Autodesk Fusion 360 part; units mm, degrees
(part 2 of 3)
  line L481 (-33.9792, -15.627) -> (-34.3891, -16.0335)
  line L482 (-34.3891, -16.0335) -> (-34.1021, -16.6352)
  line L483 (-34.1021, -16.6352) -> (-33.5283, -16.5724)
  line L484 (-33.5283, -16.5724) -> (-33.2756, -16.7004)
  line L485 (-33.2756, -16.7004) -> (-33.1305, -16.8808)
  line L486 (-33.1305, -16.8808) -> (-33.0698, -17.1043)
  line L487 (-33.0698, -17.1043) -> (-33.1148, -17.3839)
  line L488 (-33.1148, -17.3839) -> (-33.5029, -17.8113)
  line L489 (-33.5029, -17.8113) -> (-33.1848, -18.3972)
  line L490 (-33.1848, -18.3972) -> (-32.615, -18.3045)
  line L491 (-32.615, -18.3045) -> (-32.3559, -18.419)
  line L492 (-32.3559, -18.419) -> (-32.2016, -18.5916)
  line L493 (-32.2016, -18.5916) -> (-32.1293, -18.8116)
  line L494 (-32.1293, -18.8116) -> (-32.1596, -19.0932)
  line L495 (-32.1596, -19.0932) -> (-32.5248, -19.5403)
  line L496 (-32.5248, -19.5403) -> (-32.1765, -20.1087)
  line L497 (-32.1765, -20.1087) -> (-31.6123, -19.9863)
  line L498 (-31.6123, -19.9863) -> (-31.3476, -20.0871)
  line L499 (-31.3476, -20.0871) -> (-31.1844, -20.2514)
  line L500 (-31.1844, -20.2514) -> (-31.1007, -20.4673)
  line L501 (-31.1007, -20.4673) -> (-31.1163, -20.7501)
  line L502 (-31.1163, -20.7501) -> (-31.4576, -21.2157)
  line L503 (-31.4576, -21.2157) -> (-31.08, -21.7651)
  line L504 (-31.08, -21.7651) -> (-30.523, -21.6134)
  line L505 (-30.523, -21.6134) -> (-30.2534, -21.7002)
  line L506 (-30.2534, -21.7002) -> (-30.0818, -21.8557)
  line L507 (-30.0818, -21.8557) -> (-29.9869, -22.067)
  line L508 (-29.9869, -22.067) -> (-29.9877, -22.3502)
  line L509 (-29.9877, -22.3502) -> (-30.3041, -22.833)
  line L510 (-30.3041, -22.833) -> (-29.8983, -23.3619)
  line L511 (-29.8983, -23.3619) -> (-29.35, -23.1812)
  line L512 (-29.35, -23.1812) -> (-29.0762, -23.2538)
  line L513 (-29.0762, -23.2538) -> (-28.8968, -23.4001)
  line L514 (-28.8968, -23.4001) -> (-28.7909, -23.6061)
  line L515 (-28.7909, -23.6061) -> (-28.7769, -23.889)
  line L516 (-28.7769, -23.889) -> (-29.0676, -24.3877)
  line L517 (-29.0676, -24.3877) -> (-28.6346, -24.8947)
  line L518 (-28.6346, -24.8947) -> (-28.0966, -24.6855)
  line L519 (-28.0966, -24.6855) -> (-27.8194, -24.7437)
  line L520 (-27.8194, -24.7437) -> (-27.6325, -24.8804)
  line L521 (-27.6325, -24.8804) -> (-27.516, -25.0806)
  line L522 (-27.516, -25.0806) -> (-27.4872, -25.3623)
  line L523 (-27.4872, -25.3623) -> (-27.7514, -25.8756)
  line L524 (-27.7514, -25.8756) -> (-27.2925, -26.3592)
  line L525 (-27.2925, -26.3592) -> (-26.7661, -26.1221)
  line L526 (-26.7661, -26.1221) -> (-26.4863, -26.1657)
  line L527 (-26.4863, -26.1657) -> (-26.2925, -26.2925)
  line L528 (-26.2925, -26.2925) -> (-26.1657, -26.4863)
  line L529 (-26.1657, -26.4863) -> (-26.1221, -26.7661)
  line L530 (-26.1221, -26.7661) -> (-26.3592, -27.2925)
  line L531 (-26.3592, -27.2925) -> (-25.8756, -27.7514)
  line L532 (-25.8756, -27.7514) -> (-25.3623, -27.4872)
  line L533 (-25.3623, -27.4872) -> (-25.0806, -27.516)
  line L534 (-25.0806, -27.516) -> (-24.8804, -27.6325)
  line L535 (-24.8804, -27.6325) -> (-24.7437, -27.8194)
  line L536 (-24.7437, -27.8194) -> (-24.6855, -28.0966)
  line L537 (-24.6855, -28.0966) -> (-24.8947, -28.6346)
  line L538 (-24.8947, -28.6346) -> (-24.3877, -29.0676)
  line L539 (-24.3877, -29.0676) -> (-23.889, -28.7769)
  line L540 (-23.889, -28.7769) -> (-23.6061, -28.7909)
  line L541 (-23.6061, -28.7909) -> (-23.4001, -28.8968)
  line L542 (-23.4001, -28.8968) -> (-23.2538, -29.0762)
  line L543 (-23.2538, -29.0762) -> (-23.1812, -29.35)
  line L544 (-23.1812, -29.35) -> (-23.3619, -29.8983)
  line L545 (-23.3619, -29.8983) -> (-22.833, -30.3041)
  line L546 (-22.833, -30.3041) -> (-22.3502, -29.9877)
  line L547 (-22.3502, -29.9877) -> (-22.067, -29.9869)
  line L548 (-22.067, -29.9869) -> (-21.8557, -30.0818)
  line L549 (-21.8557, -30.0818) -> (-21.7002, -30.2534)
  line L550 (-21.7002, -30.2534) -> (-21.6134, -30.523)
  line L551 (-21.6134, -30.523) -> (-21.7651, -31.08)
  line L552 (-21.7651, -31.08) -> (-21.2157, -31.4576)
  line L553 (-21.2157, -31.4576) -> (-20.7501, -31.1163)
  line L554 (-20.7501, -31.1163) -> (-20.4673, -31.1007)
  line L555 (-20.4673, -31.1007) -> (-20.2514, -31.1844)
  line L556 (-20.2514, -31.1844) -> (-20.0871, -31.3476)
  line L557 (-20.0871, -31.3476) -> (-19.9863, -31.6123)
  line L558 (-19.9863, -31.6123) -> (-20.1087, -32.1765)
  line L559 (-20.1087, -32.1765) -> (-19.5403, -32.5248)
  line L560 (-19.5403, -32.5248) -> (-19.0932, -32.1596)
  line L561 (-19.0932, -32.1596) -> (-18.8116, -32.1293)
  line L562 (-18.8116, -32.1293) -> (-18.5916, -32.2016)
  line L563 (-18.5916, -32.2016) -> (-18.419, -32.3559)
  line L564 (-18.419, -32.3559) -> (-18.3045, -32.615)
  line L565 (-18.3045, -32.615) -> (-18.3972, -33.1848)
  line L566 (-18.3972, -33.1848) -> (-17.8113, -33.5029)
  line L567 (-17.8113, -33.5029) -> (-17.3839, -33.1148)
  line L568 (-17.3839, -33.1148) -> (-17.1043, -33.0698)
  line L569 (-17.1043, -33.0698) -> (-16.8808, -33.1305)
  line L570 (-16.8808, -33.1305) -> (-16.7004, -33.2756)
  line L571 (-16.7004, -33.2756) -> (-16.5724, -33.5283)
  line L572 (-16.5724, -33.5283) -> (-16.6352, -34.1021)
  line L573 (-16.6352, -34.1021) -> (-16.0335, -34.3891)
  line L574 (-16.0335, -34.3891) -> (-15.627, -33.9792)
  line L575 (-15.627, -33.9792) -> (-15.3501, -33.9196)
  line L576 (-15.3501, -33.9196) -> (-15.1238, -33.9685)
  line L577 (-15.1238, -33.9685) -> (-14.936, -34.104)
  line L578 (-14.936, -34.104) -> (-14.795, -34.3497)
  line L579 (-14.795, -34.3497) -> (-14.8276, -34.926)
  line L580 (-14.8276, -34.926) -> (-14.2117, -35.1811)
  line L581 (-14.2117, -35.1811) -> (-13.8273, -34.7505)
  line L582 (-13.8273, -34.7505) -> (-13.5539, -34.6765)
  line L583 (-13.5539, -34.6765) -> (-13.3253, -34.7135)
  line L584 (-13.3253, -34.7135) -> (-13.1306, -34.839)
  line L585 (-13.1306, -34.839) -> (-12.977, -35.0769)
  line L586 (-12.977, -35.0769) -> (-12.9794, -35.6542)
  line L587 (-12.9794, -35.6542) -> (-12.351, -35.8767)
  line L588 (-12.351, -35.8767) -> (-11.9896, -35.4266)
  line L589 (-11.9896, -35.4266) -> (-11.7204, -35.3383)
  line L590 (-11.7204, -35.3383) -> (-11.4902, -35.3633)
  line L591 (-11.4902, -35.3633) -> (-11.2893, -35.4784)
  line L592 (-11.2893, -35.4784) -> (-11.1234, -35.708)
  line L593 (-11.1234, -35.708) -> (-11.0956, -36.2846)
  line L594 (-11.0956, -36.2846) -> (-10.4564, -36.4739)
  line L595 (-10.4564, -36.4739) -> (-10.1191, -36.0055)
  line L596 (-10.1191, -36.0055) -> (-9.8549, -35.9033)
  line L597 (-9.8549, -35.9033) -> (-9.6237, -35.9162)
  line L598 (-9.6237, -35.9162) -> (-9.417, -36.0206)
  line L599 (-9.417, -36.0206) -> (-9.2394, -36.2412)
  line L600 (-9.2394, -36.2412) -> (-9.1815, -36.8156)
  line L601 (-9.1815, -36.8156) -> (-8.5332, -36.9712)
  line L602 (-8.5332, -36.9712) -> (-8.2208, -36.4858)
  line L603 (-8.2208, -36.4858) -> (-7.9624, -36.3699)
  line L604 (-7.9624, -36.3699) -> (-7.7308, -36.3706)
  line L605 (-7.7308, -36.3706) -> (-7.519, -36.4641)
  line L606 (-7.519, -36.4641) -> (-7.33, -36.6751)
  line L607 (-7.33, -36.6751) -> (-7.2421, -37.2456)
  line L608 (-7.2421, -37.2456) -> (-6.5866, -37.3671)
  line L609 (-6.5866, -37.3671) -> (-6.3001, -36.866)
  line L610 (-6.3001, -36.866) -> (-6.048, -36.7367)
  line L611 (-6.048, -36.7367) -> (-5.8167, -36.7254)
  line L612 (-5.8167, -36.7254) -> (-5.6003, -36.8077)
  line L613 (-5.6003, -36.8077) -> (-5.4005, -37.0085)
  line L614 (-5.4005, -37.0085) -> (-5.2829, -37.5736)
  line L615 (-5.2829, -37.5736) -> (-4.6219, -37.6606)
  line L616 (-4.6219, -37.6606) -> (-4.362, -37.1452)
  line L617 (-4.362, -37.1452) -> (-4.1171, -37.0029)
  line L618 (-4.1171, -37.0029) -> (-3.8867, -36.9795)
  line L619 (-3.8867, -36.9795) -> (-3.6662, -37.0503)
  line L620 (-3.6662, -37.0503) -> (-3.4562, -37.2404)
  line L621 (-3.4562, -37.2404) -> (-3.3092, -37.7986)
  line L622 (-3.3092, -37.7986) -> (-2.6446, -37.8509)
  line L623 (-2.6446, -37.8509) -> (-2.412, -37.3226)
  line L624 (-2.412, -37.3226) -> (-2.1749, -37.1677)
  line L625 (-2.1749, -37.1677) -> (-1.946, -37.1322)
  line L626 (-1.946, -37.1322) -> (-1.7221, -37.1914)
  line L627 (-1.7221, -37.1914) -> (-1.5025, -37.3702)
  line L628 (-1.5025, -37.3702) -> (-1.3264, -37.92)
  line L629 (-1.3264, -37.92) -> (-0.66, -37.9374)
  line L630 (-0.66, -37.9374) -> (-0.4554, -37.3977)
  line L631 (-0.4554, -37.3977) -> (-0.2267, -37.2306)
  line L632 (-0.2267, -37.2306) -> (0, -37.1832)
  line L633 (0, -37.1832) -> (0.2267, -37.2306)
  line L634 (0.2267, -37.2306) -> (0.4554, -37.3977)
  line L635 (0.4554, -37.3977) -> (0.66, -37.9374)
  line L636 (0.66, -37.9374) -> (1.3264, -37.92)
  line L637 (1.3264, -37.92) -> (1.5025, -37.3702)
  line L638 (1.5025, -37.3702) -> (1.7221, -37.1914)
  line L639 (1.7221, -37.1914) -> (1.946, -37.1322)
  line L640 (1.946, -37.1322) -> (2.1749, -37.1677)
  line L641 (2.1749, -37.1677) -> (2.412, -37.3226)
  line L642 (2.412, -37.3226) -> (2.6446, -37.8509)
  line L643 (2.6446, -37.8509) -> (3.3092, -37.7986)
  line L644 (3.3092, -37.7986) -> (3.4562, -37.2404)
  line L645 (3.4562, -37.2404) -> (3.6662, -37.0503)
  line L646 (3.6662, -37.0503) -> (3.8867, -36.9795)
  line L647 (3.8867, -36.9795) -> (4.1171, -37.0029)
  line L648 (4.1171, -37.0029) -> (4.362, -37.1452)
  line L649 (4.362, -37.1452) -> (4.6219, -37.6606)
  line L650 (4.6219, -37.6606) -> (5.2829, -37.5736)
  line L651 (5.2829, -37.5736) -> (5.4005, -37.0085)
  line L652 (5.4005, -37.0085) -> (5.6003, -36.8077)
  line L653 (5.6003, -36.8077) -> (5.8167, -36.7254)
  line L654 (5.8167, -36.7254) -> (6.048, -36.7367)
  line L655 (6.048, -36.7367) -> (6.3001, -36.866)
  line L656 (6.3001, -36.866) -> (6.5866, -37.3671)
  line L657 (6.5866, -37.3671) -> (7.2421, -37.2456)
  line L658 (7.2421, -37.2456) -> (7.33, -36.6751)
  line L659 (7.33, -36.6751) -> (7.519, -36.4641)
  line L660 (7.519, -36.4641) -> (7.7308, -36.3706)
  line L661 (7.7308, -36.3706) -> (7.9624, -36.3699)
  line L662 (7.9624, -36.3699) -> (8.2208, -36.4858)
  line L663 (8.2208, -36.4858) -> (8.5332, -36.9712)
  line L664 (8.5332, -36.9712) -> (9.1815, -36.8156)
  line L665 (9.1815, -36.8156) -> (9.2394, -36.2412)
  line L666 (9.2394, -36.2412) -> (9.417, -36.0206)
  line L667 (9.417, -36.0206) -> (9.6237, -35.9162)
  line L668 (9.6237, -35.9162) -> (9.8549, -35.9033)
  line L669 (9.8549, -35.9033) -> (10.1191, -36.0055)
  line L670 (10.1191, -36.0055) -> (10.4564, -36.4739)
  line L671 (10.4564, -36.4739) -> (11.0956, -36.2846)
  line L672 (11.0956, -36.2846) -> (11.1234, -35.708)
  line L673 (11.1234, -35.708) -> (11.2893, -35.4784)
  line L674 (11.2893, -35.4784) -> (11.4902, -35.3633)
  line L675 (11.4902, -35.3633) -> (11.7204, -35.3383)
  line L676 (11.7204, -35.3383) -> (11.9896, -35.4266)
  line L677 (11.9896, -35.4266) -> (12.351, -35.8767)
  line L678 (12.351, -35.8767) -> (12.9794, -35.6542)
  line L679 (12.9794, -35.6542) -> (12.977, -35.0769)
  line L680 (12.977, -35.0769) -> (13.1306, -34.839)
  line L681 (13.1306, -34.839) -> (13.3253, -34.7135)
  line L682 (13.3253, -34.7135) -> (13.5539, -34.6765)
  line L683 (13.5539, -34.6765) -> (13.8273, -34.7505)
  line L684 (13.8273, -34.7505) -> (14.2117, -35.1811)
  line L685 (14.2117, -35.1811) -> (14.8276, -34.926)
  line L686 (14.8276, -34.926) -> (14.795, -34.3497)
  line L687 (14.795, -34.3497) -> (14.936, -34.104)
  line L688 (14.936, -34.104) -> (15.1238, -33.9685)
  line L689 (15.1238, -33.9685) -> (15.3501, -33.9196)
  line L690 (15.3501, -33.9196) -> (15.627, -33.9792)
  line L691 (15.627, -33.9792) -> (16.0335, -34.3891)
  line L692 (16.0335, -34.3891) -> (16.6352, -34.1021)
  line L693 (16.6352, -34.1021) -> (16.5724, -33.5283)
  line L694 (16.5724, -33.5283) -> (16.7004, -33.2756)
  line L695 (16.7004, -33.2756) -> (16.8808, -33.1305)
  line L696 (16.8808, -33.1305) -> (17.1043, -33.0698)
  line L697 (17.1043, -33.0698) -> (17.3839, -33.1148)
  line L698 (17.3839, -33.1148) -> (17.8113, -33.5029)
  line L699 (17.8113, -33.5029) -> (18.3972, -33.1848)
  line L700 (18.3972, -33.1848) -> (18.3045, -32.615)
  line L701 (18.3045, -32.615) -> (18.419, -32.3559)
  line L702 (18.419, -32.3559) -> (18.5916, -32.2016)
  line L703 (18.5916, -32.2016) -> (18.8116, -32.1293)
  line L704 (18.8116, -32.1293) -> (19.0932, -32.1596)
  line L705 (19.0932, -32.1596) -> (19.5403, -32.5248)
  line L706 (19.5403, -32.5248) -> (20.1087, -32.1765)
  line L707 (20.1087, -32.1765) -> (19.9863, -31.6123)
  line L708 (19.9863, -31.6123) -> (20.0871, -31.3476)
  line L709 (20.0871, -31.3476) -> (20.2514, -31.1844)
  line L710 (20.2514, -31.1844) -> (20.4673, -31.1007)
  line L711 (20.4673, -31.1007) -> (20.7501, -31.1163)
  line L712 (20.7501, -31.1163) -> (21.2157, -31.4576)
  line L713 (21.2157, -31.4576) -> (21.7651, -31.08)
  line L714 (21.7651, -31.08) -> (21.6134, -30.523)
  line L715 (21.6134, -30.523) -> (21.7002, -30.2534)
  line L716 (21.7002, -30.2534) -> (21.8557, -30.0818)
  line L717 (21.8557, -30.0818) -> (22.067, -29.9869)
  line L718 (22.067, -29.9869) -> (22.3502, -29.9877)
  line L719 (22.3502, -29.9877) -> (22.833, -30.3041)
  line L720 (22.833, -30.3041) -> (23.3619, -29.8983)
  line L721 (23.3619, -29.8983) -> (23.1812, -29.35)
  line L722 (23.1812, -29.35) -> (23.2538, -29.0762)
  line L723 (23.2538, -29.0762) -> (23.4001, -28.8968)
  line L724 (23.4001, -28.8968) -> (23.6061, -28.7909)
  line L725 (23.6061, -28.7909) -> (23.889, -28.7769)
  line L726 (23.889, -28.7769) -> (24.3877, -29.0676)
  line L727 (24.3877, -29.0676) -> (24.8947, -28.6346)
  line L728 (24.8947, -28.6346) -> (24.6855, -28.0966)
  line L729 (24.6855, -28.0966) -> (24.7437, -27.8194)
  line L730 (24.7437, -27.8194) -> (24.8804, -27.6325)
  line L731 (24.8804, -27.6325) -> (25.0806, -27.516)
  line L732 (25.0806, -27.516) -> (25.3623, -27.4872)
  line L733 (25.3623, -27.4872) -> (25.8756, -27.7514)
  line L734 (25.8756, -27.7514) -> (26.3592, -27.2925)
  line L735 (26.3592, -27.2925) -> (26.1221, -26.7661)
  line L736 (26.1221, -26.7661) -> (26.1657, -26.4863)
  line L737 (26.1657, -26.4863) -> (26.2925, -26.2925)
  line L738 (26.2925, -26.2925) -> (26.4863, -26.1657)
  line L739 (26.4863, -26.1657) -> (26.7661, -26.1221)
  line L740 (26.7661, -26.1221) -> (27.2925, -26.3592)
  line L741 (27.2925, -26.3592) -> (27.7514, -25.8756)
  line L742 (27.7514, -25.8756) -> (27.4872, -25.3623)
  line L743 (27.4872, -25.3623) -> (27.516, -25.0806)
  line L744 (27.516, -25.0806) -> (27.6325, -24.8804)
  line L745 (27.6325, -24.8804) -> (27.8194, -24.7437)
  line L746 (27.8194, -24.7437) -> (28.0966, -24.6855)
  line L747 (28.0966, -24.6855) -> (28.6346, -24.8947)
  line L748 (28.6346, -24.8947) -> (29.0676, -24.3877)
  line L749 (29.0676, -24.3877) -> (28.7769, -23.889)
  line L750 (28.7769, -23.889) -> (28.7909, -23.6061)
  line L751 (28.7909, -23.6061) -> (28.8968, -23.4001)
  line L752 (28.8968, -23.4001) -> (29.0762, -23.2538)
  line L753 (29.0762, -23.2538) -> (29.35, -23.1812)
  line L754 (29.35, -23.1812) -> (29.8983, -23.3619)
  line L755 (29.8983, -23.3619) -> (30.3041, -22.833)
  line L756 (30.3041, -22.833) -> (29.9877, -22.3502)
  line L757 (29.9877, -22.3502) -> (29.9869, -22.067)
  line L758 (29.9869, -22.067) -> (30.0818, -21.8557)
  line L759 (30.0818, -21.8557) -> (30.2534, -21.7002)
  line L760 (30.2534, -21.7002) -> (30.523, -21.6134)
  line L761 (30.523, -21.6134) -> (31.08, -21.7651)
  line L762 (31.08, -21.7651) -> (31.4576, -21.2157)
  line L763 (31.4576, -21.2157) -> (31.1163, -20.7501)
  line L764 (31.1163, -20.7501) -> (31.1007, -20.4673)
  line L765 (31.1007, -20.4673) -> (31.1844, -20.2514)
  line L766 (31.1844, -20.2514) -> (31.3476, -20.0871)
  line L767 (31.3476, -20.0871) -> (31.6123, -19.9863)
  line L768 (31.6123, -19.9863) -> (32.1765, -20.1087)
  line L769 (32.1765, -20.1087) -> (32.5248, -19.5403)
  line L770 (32.5248, -19.5403) -> (32.1596, -19.0932)
  line L771 (32.1596, -19.0932) -> (32.1293, -18.8116)
  line L772 (32.1293, -18.8116) -> (32.2016, -18.5916)
  line L773 (32.2016, -18.5916) -> (32.3559, -18.419)
  line L774 (32.3559, -18.419) -> (32.615, -18.3045)
  line L775 (32.615, -18.3045) -> (33.1848, -18.3972)
  line L776 (33.1848, -18.3972) -> (33.5029, -17.8113)
  line L777 (33.5029, -17.8113) -> (33.1148, -17.3839)
  line L778 (33.1148, -17.3839) -> (33.0698, -17.1043)
  line L779 (33.0698, -17.1043) -> (33.1305, -16.8808)
  line L780 (33.1305, -16.8808) -> (33.2756, -16.7004)
  line L781 (33.2756, -16.7004) -> (33.5283, -16.5724)
  line L782 (33.5283, -16.5724) -> (34.1021, -16.6352)
  line L783 (34.1021, -16.6352) -> (34.3891, -16.0335)
  line L784 (34.3891, -16.0335) -> (33.9792, -15.627)
  line L785 (33.9792, -15.627) -> (33.9196, -15.3501)
  line L786 (33.9196, -15.3501) -> (33.9685, -15.1238)
  line L787 (33.9685, -15.1238) -> (34.104, -14.936)
  line L788 (34.104, -14.936) -> (34.3497, -14.795)
  line L789 (34.3497, -14.795) -> (34.926, -14.8276)
  line L790 (34.926, -14.8276) -> (35.1811, -14.2117)
  line L791 (35.1811, -14.2117) -> (34.7505, -13.8273)
  line L792 (34.7505, -13.8273) -> (34.6765, -13.5539)
  line L793 (34.6765, -13.5539) -> (34.7135, -13.3253)
  line L794 (34.7135, -13.3253) -> (34.839, -13.1306)
  line L795 (34.839, -13.1306) -> (35.0769, -12.977)
  line L796 (35.0769, -12.977) -> (35.6542, -12.9794)
  line L797 (35.6542, -12.9794) -> (35.8767, -12.351)
  line L798 (35.8767, -12.351) -> (35.4266, -11.9896)
  line L799 (35.4266, -11.9896) -> (35.3383, -11.7204)
  line L800 (35.3383, -11.7204) -> (35.3633, -11.4902)
  line L801 (35.3633, -11.4902) -> (35.4784, -11.2893)
  line L802 (35.4784, -11.2893) -> (35.708, -11.1234)
  line L803 (35.708, -11.1234) -> (36.2846, -11.0956)
  line L804 (36.2846, -11.0956) -> (36.4739, -10.4564)
  line L805 (36.4739, -10.4564) -> (36.0055, -10.1191)
  line L806 (36.0055, -10.1191) -> (35.9033, -9.8549)
  line L807 (35.9033, -9.8549) -> (35.9162, -9.6237)
  line L808 (35.9162, -9.6237) -> (36.0206, -9.417)
  line L809 (36.0206, -9.417) -> (36.2412, -9.2394)
  line L810 (36.2412, -9.2394) -> (36.8156, -9.1815)
  line L811 (36.8156, -9.1815) -> (36.9712, -8.5332)
  line L812 (36.9712, -8.5332) -> (36.4858, -8.2208)
  line L813 (36.4858, -8.2208) -> (36.3699, -7.9624)
  line L814 (36.3699, -7.9624) -> (36.3706, -7.7308)
  line L815 (36.3706, -7.7308) -> (36.4641, -7.519)
  line L816 (36.4641, -7.519) -> (36.6751, -7.33)
  line L817 (36.6751, -7.33) -> (37.2456, -7.2421)
  line L818 (37.2456, -7.2421) -> (37.3671, -6.5866)
  line L819 (37.3671, -6.5866) -> (36.866, -6.3001)
  line L820 (36.866, -6.3001) -> (36.7367, -6.048)
  line L821 (36.7367, -6.048) -> (36.7254, -5.8167)
  line L822 (36.7254, -5.8167) -> (36.8077, -5.6003)
  line L823 (36.8077, -5.6003) -> (37.0085, -5.4005)
  line L824 (37.0085, -5.4005) -> (37.5736, -5.2829)
  line L825 (37.5736, -5.2829) -> (37.6606, -4.6219)
  line L826 (37.6606, -4.6219) -> (37.1452, -4.362)
  line L827 (37.1452, -4.362) -> (37.0029, -4.1171)
  line L828 (37.0029, -4.1171) -> (36.9795, -3.8867)
  line L829 (36.9795, -3.8867) -> (37.0503, -3.6662)
  line L830 (37.0503, -3.6662) -> (37.2404, -3.4562)
  line L831 (37.2404, -3.4562) -> (37.7986, -3.3092)
  line L832 (37.7986, -3.3092) -> (37.8509, -2.6446)
  line L833 (37.8509, -2.6446) -> (37.3226, -2.412)
  line L834 (37.3226, -2.412) -> (37.1677, -2.1749)
  line L835 (37.1677, -2.1749) -> (37.1322, -1.946)
  line L836 (37.1322, -1.946) -> (37.1914, -1.7221)
  line L837 (37.1914, -1.7221) -> (37.3702, -1.5025)
  line L838 (37.3702, -1.5025) -> (37.92, -1.3264)
  line L839 (37.92, -1.3264) -> (37.9374, -0.66)
extrude "Extrude1''''''''''" add sketch "Sketch1 (11)" along normal blind 11 separate body makes body 11 in component "print_pulley_120T"
ref_plane "WorkPlane2" through (0, 0, 7.5) normal (0, 0, 1) x (1, 0, 0) in component "print_pulley_120T"
sketch "Sketch2 (11)" plane through (0, 0, 7.5) normal (0, 0, 1) x (1, 0, 0) in component "print_pulley_120T"
  line L0 (14.607, 0) -> (7.3035, 12.65)
  line L1 (7.3035, 12.65) -> (-7.3035, 12.65)
  line L2 (-7.3035, 12.65) -> (-14.607, 0)
  line L3 (-14.607, 0) -> (-7.3035, -12.65)
  line L4 (-7.3035, -12.65) -> (7.3035, -12.65)
  line L5 (7.3035, -12.65) -> (14.607, 0)
extrude "Extrude2''''''''''" cut sketch "Sketch2 (11)" along normal blind 11 bodies 11 in component "print_pulley_120T"
ref_plane "WorkPlane1" through (0, 0, 7.5) normal (0, 0, 1) x (1, 0, 0) in component "print_pulley_100T"
sketch "Sketch1 (12)" plane through (0, 0, 7.5) normal (0, 0, 1) x (1, 0, 0) in component "print_pulley_100T"
  line L0 (31.5701, -0.66) -> (31.0309, -0.454)
  line L1 (31.0309, -0.454) -> (30.8642, -0.2258)
  line L2 (30.8642, -0.2258) -> (30.817, 0)
  line L3 (30.817, 0) -> (30.8642, 0.2258)
  line L4 (30.8642, 0.2258) -> (31.0309, 0.454)
  line L5 (31.0309, 0.454) -> (31.5701, 0.66)
  line L6 (31.5701, 0.66) -> (31.5492, 1.3237)
  line L7 (31.5492, 1.3237) -> (30.9982, 1.4953)
  line L8 (30.9982, 1.4953) -> (30.8175, 1.7126)
  line L9 (30.8175, 1.7126) -> (30.7562, 1.935)
  line L10 (30.7562, 1.935) -> (30.7892, 2.1633)
  line L11 (30.7892, 2.1633) -> (30.9412, 2.4016)
  line L12 (30.9412, 2.4016) -> (31.4664, 2.641)
  line L13 (31.4664, 2.641) -> (31.4039, 3.302)
  line L14 (31.4039, 3.302) -> (30.8431, 3.4387)
  line L15 (30.8431, 3.4387) -> (30.6492, 3.6443)
  line L16 (30.6492, 3.6443) -> (30.574, 3.8624)
  line L17 (30.574, 3.8624) -> (30.5926, 4.0923)
  line L18 (30.5926, 4.0923) -> (30.7293, 4.3397)
  line L19 (30.7293, 4.3397) -> (31.2384, 4.6115)
  line L20 (31.2384, 4.6115) -> (31.1346, 5.2674)
  line L21 (31.1346, 5.2674) -> (30.5664, 5.3686)
  line L22 (30.5664, 5.3686) -> (30.3599, 5.5616)
  line L23 (30.3599, 5.5616) -> (30.2711, 5.7745)
  line L24 (30.2711, 5.7745) -> (30.2752, 6.0052)
  line L25 (30.2752, 6.0052) -> (30.3962, 6.2606)
  line L26 (30.3962, 6.2606) -> (30.8872, 6.5639)
  line L27 (30.8872, 6.5639) -> (30.7424, 7.2119)
  line L28 (30.7424, 7.2119) -> (30.1689, 7.2773)
  line L29 (30.1689, 7.2773) -> (29.9507, 7.4569)
  line L30 (29.9507, 7.4569) -> (29.8488, 7.6639)
  line L31 (29.8488, 7.6639) -> (29.8384, 7.8943)
  line L32 (29.8384, 7.8943) -> (29.9431, 8.1569)
  line L33 (29.9431, 8.1569) -> (30.4141, 8.4904)
  line L34 (30.4141, 8.4904) -> (30.2289, 9.128)
  line L35 (30.2289, 9.128) -> (29.6525, 9.1573)
  line L36 (29.6525, 9.1573) -> (29.4234, 9.3228)
  line L37 (29.4234, 9.3228) -> (29.3087, 9.523)
  line L38 (29.3087, 9.523) -> (29.2839, 9.7523)
  line L39 (29.2839, 9.7523) -> (29.3719, 10.0209)
  line L40 (29.3719, 10.0209) -> (29.821, 10.3833)
  line L41 (29.821, 10.3833) -> (29.5961, 11.0081)
  line L42 (29.5961, 11.0081) -> (29.019, 11.0011)
  line L43 (29.019, 11.0011) -> (28.78, 11.1519)
  line L44 (28.78, 11.1519) -> (28.6529, 11.3445)
  line L45 (28.6529, 11.3445) -> (28.6137, 11.5718)
  line L46 (28.6137, 11.5718) -> (28.6847, 11.8454)
  line L47 (28.6847, 11.8454) -> (29.1102, 12.2353)
  line L48 (29.1102, 12.2353) -> (28.8465, 12.8447)
  line L49 (28.8465, 12.8447) -> (28.2709, 12.8015)
  line L50 (28.2709, 12.8015) -> (28.0229, 12.9371)
  line L51 (28.0229, 12.9371) -> (27.884, 13.1212)
  line L52 (27.884, 13.1212) -> (27.8307, 13.3457)
  line L53 (27.8307, 13.3457) -> (27.8843, 13.6232)
  line L54 (27.8843, 13.6232) -> (28.2845, 14.039)
  line L55 (28.2845, 14.039) -> (27.983, 14.6307)
  line L56 (27.983, 14.6307) -> (27.4113, 14.5514)
  line L57 (27.4113, 14.5514) -> (27.1553, 14.6711)
  line L58 (27.1553, 14.6711) -> (27.0051, 14.8462)
  line L59 (27.0051, 14.8462) -> (26.9378, 15.0668)
  line L60 (26.9378, 15.0668) -> (26.9739, 15.3471)
  line L61 (26.9739, 15.3471) -> (27.3471, 15.7873)
  line L62 (27.3471, 15.7873) -> (27.0091, 16.3589)
  line L63 (27.0091, 16.3589) -> (26.4436, 16.2438)
  line L64 (26.4436, 16.2438) -> (26.1805, 16.3472)
  line L65 (26.1805, 16.3472) -> (26.0196, 16.5126)
  line L66 (26.0196, 16.5126) -> (25.9385, 16.7285)
  line L67 (25.9385, 16.7285) -> (25.957, 17.0106)
  line L68 (25.957, 17.0106) -> (26.3019, 17.4733)
  line L69 (26.3019, 17.4733) -> (25.9287, 18.0225)
  line L70 (25.9287, 18.0225) -> (25.3714, 17.8722)
  line L71 (25.3714, 17.8722) -> (25.1024, 17.9589)
  line L72 (25.1024, 17.9589) -> (24.9315, 18.1138)
  line L73 (24.9315, 18.1138) -> (24.837, 18.3242)
  line L74 (24.837, 18.3242) -> (24.8377, 18.6068)
  line L75 (24.8377, 18.6068) -> (25.1528, 19.0903)
  line L76 (25.1528, 19.0903) -> (24.7458, 19.615)
  line L77 (24.7458, 19.615) -> (24.1992, 19.43)
  line L78 (24.1992, 19.43) -> (23.9252, 19.4996)
  line L79 (23.9252, 19.4996) -> (23.7449, 19.6435)
  line L80 (23.7449, 19.6435) -> (23.6374, 19.8476)
  line L81 (23.6374, 19.8476) -> (23.6203, 20.1297)
  line L82 (23.6203, 20.1297) -> (23.9045, 20.632)
  line L83 (23.9045, 20.632) -> (23.4654, 21.1301)
  line L84 (23.4654, 21.1301) -> (22.9314, 20.9111)
  line L85 (22.9314, 20.9111) -> (22.6536, 20.9634)
  line L86 (22.6536, 20.9634) -> (22.4646, 21.0957)
  line L87 (22.4646, 21.0957) -> (22.3445, 21.2926)
  line L88 (22.3445, 21.2926) -> (22.3098, 21.5731)
  line L89 (22.3098, 21.5731) -> (22.5618, 22.0923)
  line L90 (22.5618, 22.0923) -> (22.0923, 22.5618)
  line L91 (22.0923, 22.5618) -> (21.5731, 22.3098)
  line L92 (21.5731, 22.3098) -> (21.2926, 22.3445)
  line L93 (21.2926, 22.3445) -> (21.0957, 22.4646)
  line L94 (21.0957, 22.4646) -> (20.9634, 22.6536)
  line L95 (20.9634, 22.6536) -> (20.9111, 22.9314)
  line L96 (20.9111, 22.9314) -> (21.1301, 23.4654)
  line L97 (21.1301, 23.4654) -> (20.632, 23.9045)
  line L98 (20.632, 23.9045) -> (20.1297, 23.6203)
  line L99 (20.1297, 23.6203) -> (19.8476, 23.6374)
  line L100 (19.8476, 23.6374) -> (19.6435, 23.7449)
  line L101 (19.6435, 23.7449) -> (19.4996, 23.9252)
  line L102 (19.4996, 23.9252) -> (19.43, 24.1992)
  line L103 (19.43, 24.1992) -> (19.615, 24.7458)
  line L104 (19.615, 24.7458) -> (19.0903, 25.1528)
  line L105 (19.0903, 25.1528) -> (18.6068, 24.8377)
  line L106 (18.6068, 24.8377) -> (18.3242, 24.837)
  line L107 (18.3242, 24.837) -> (18.1138, 24.9315)
  line L108 (18.1138, 24.9315) -> (17.9589, 25.1024)
  line L109 (17.9589, 25.1024) -> (17.8722, 25.3714)
  line L110 (17.8722, 25.3714) -> (18.0225, 25.9287)
  line L111 (18.0225, 25.9287) -> (17.4733, 26.3019)
  line L112 (17.4733, 26.3019) -> (17.0106, 25.957)
  line L113 (17.0106, 25.957) -> (16.7285, 25.9385)
  line L114 (16.7285, 25.9385) -> (16.5126, 26.0196)
  line L115 (16.5126, 26.0196) -> (16.3472, 26.1805)
  line L116 (16.3472, 26.1805) -> (16.2438, 26.4436)
  line L117 (16.2438, 26.4436) -> (16.3589, 27.0091)
  line L118 (16.3589, 27.0091) -> (15.7873, 27.3471)
  line L119 (15.7873, 27.3471) -> (15.3471, 26.9739)
  line L120 (15.3471, 26.9739) -> (15.0668, 26.9378)
  line L121 (15.0668, 26.9378) -> (14.8462, 27.0051)
  line L122 (14.8462, 27.0051) -> (14.6711, 27.1553)
  line L123 (14.6711, 27.1553) -> (14.5514, 27.4113)
  line L124 (14.5514, 27.4113) -> (14.6307, 27.983)
  line L125 (14.6307, 27.983) -> (14.039, 28.2845)
  line L126 (14.039, 28.2845) -> (13.6232, 27.8843)
  line L127 (13.6232, 27.8843) -> (13.3457, 27.8307)
  line L128 (13.3457, 27.8307) -> (13.1212, 27.884)
  line L129 (13.1212, 27.884) -> (12.9371, 28.0229)
  line L130 (12.9371, 28.0229) -> (12.8015, 28.2709)
  line L131 (12.8015, 28.2709) -> (12.8447, 28.8465)
  line L132 (12.8447, 28.8465) -> (12.2353, 29.1102)
  line L133 (12.2353, 29.1102) -> (11.8454, 28.6847)
  line L134 (11.8454, 28.6847) -> (11.5718, 28.6137)
  line L135 (11.5718, 28.6137) -> (11.3445, 28.6529)
  line L136 (11.3445, 28.6529) -> (11.1519, 28.78)
  line L137 (11.1519, 28.78) -> (11.0011, 29.019)
  line L138 (11.0011, 29.019) -> (11.0081, 29.5961)
  line L139 (11.0081, 29.5961) -> (10.3833, 29.821)
  line L140 (10.3833, 29.821) -> (10.0209, 29.3719)
  line L141 (10.0209, 29.3719) -> (9.7523, 29.2839)
  line L142 (9.7523, 29.2839) -> (9.523, 29.3087)
  line L143 (9.523, 29.3087) -> (9.3228, 29.4234)
  line L144 (9.3228, 29.4234) -> (9.1573, 29.6525)
  line L145 (9.1573, 29.6525) -> (9.128, 30.2289)
  line L146 (9.128, 30.2289) -> (8.4904, 30.4141)
  line L147 (8.4904, 30.4141) -> (8.1569, 29.9431)
  line L148 (8.1569, 29.9431) -> (7.8943, 29.8384)
  line L149 (7.8943, 29.8384) -> (7.6639, 29.8488)
  line L150 (7.6639, 29.8488) -> (7.4569, 29.9507)
  line L151 (7.4569, 29.9507) -> (7.2773, 30.1689)
  line L152 (7.2773, 30.1689) -> (7.2119, 30.7424)
  line L153 (7.2119, 30.7424) -> (6.5639, 30.8872)
  line L154 (6.5639, 30.8872) -> (6.2606, 30.3962)
  line L155 (6.2606, 30.3962) -> (6.0052, 30.2752)
  line L156 (6.0052, 30.2752) -> (5.7745, 30.2711)
  line L157 (5.7745, 30.2711) -> (5.5616, 30.3599)
  line L158 (5.5616, 30.3599) -> (5.3686, 30.5664)
  line L159 (5.3686, 30.5664) -> (5.2674, 31.1346)
  line L160 (5.2674, 31.1346) -> (4.6115, 31.2384)
  line L161 (4.6115, 31.2384) -> (4.3397, 30.7293)
  line L162 (4.3397, 30.7293) -> (4.0923, 30.5926)
  line L163 (4.0923, 30.5926) -> (3.8624, 30.574)
  line L164 (3.8624, 30.574) -> (3.6443, 30.6492)
  line L165 (3.6443, 30.6492) -> (3.4387, 30.8431)
  line L166 (3.4387, 30.8431) -> (3.302, 31.4039)
  line L167 (3.302, 31.4039) -> (2.641, 31.4664)
  line L168 (2.641, 31.4664) -> (2.4016, 30.9412)
  line L169 (2.4016, 30.9412) -> (2.1633, 30.7892)
  line L170 (2.1633, 30.7892) -> (1.935, 30.7562)
  line L171 (1.935, 30.7562) -> (1.7126, 30.8175)
  line L172 (1.7126, 30.8175) -> (1.4953, 30.9982)
  line L173 (1.4953, 30.9982) -> (1.3237, 31.5492)
  line L174 (1.3237, 31.5492) -> (0.66, 31.5701)
  line L175 (0.66, 31.5701) -> (0.454, 31.0309)
  line L176 (0.454, 31.0309) -> (0.2258, 30.8642)
  line L177 (0.2258, 30.8642) -> (0, 30.817)
  line L178 (0, 30.817) -> (-0.2258, 30.8642)
  line L179 (-0.2258, 30.8642) -> (-0.454, 31.0309)
  line L180 (-0.454, 31.0309) -> (-0.66, 31.5701)
  line L181 (-0.66, 31.5701) -> (-1.3237, 31.5492)
  line L182 (-1.3237, 31.5492) -> (-1.4953, 30.9982)
  line L183 (-1.4953, 30.9982) -> (-1.7126, 30.8175)
  line L184 (-1.7126, 30.8175) -> (-1.935, 30.7562)
  line L185 (-1.935, 30.7562) -> (-2.1633, 30.7892)
  line L186 (-2.1633, 30.7892) -> (-2.4016, 30.9412)
  line L187 (-2.4016, 30.9412) -> (-2.641, 31.4664)
  line L188 (-2.641, 31.4664) -> (-3.302, 31.4039)
  line L189 (-3.302, 31.4039) -> (-3.4387, 30.8431)
  line L190 (-3.4387, 30.8431) -> (-3.6443, 30.6492)
  line L191 (-3.6443, 30.6492) -> (-3.8624, 30.574)
  line L192 (-3.8624, 30.574) -> (-4.0923, 30.5926)
  line L193 (-4.0923, 30.5926) -> (-4.3397, 30.7293)
  line L194 (-4.3397, 30.7293) -> (-4.6115, 31.2384)
  line L195 (-4.6115, 31.2384) -> (-5.2674, 31.1346)
  line L196 (-5.2674, 31.1346) -> (-5.3686, 30.5664)
  line L197 (-5.3686, 30.5664) -> (-5.5616, 30.3599)
  line L198 (-5.5616, 30.3599) -> (-5.7745, 30.2711)
  line L199 (-5.7745, 30.2711) -> (-6.0052, 30.2752)
  line L200 (-6.0052, 30.2752) -> (-6.2606, 30.3962)
  line L201 (-6.2606, 30.3962) -> (-6.5639, 30.8872)
  line L202 (-6.5639, 30.8872) -> (-7.2119, 30.7424)
  line L203 (-7.2119, 30.7424) -> (-7.2773, 30.1689)
  line L204 (-7.2773, 30.1689) -> (-7.4569, 29.9507)
  line L205 (-7.4569, 29.9507) -> (-7.6639, 29.8488)
  line L206 (-7.6639, 29.8488) -> (-7.8943, 29.8384)
  line L207 (-7.8943, 29.8384) -> (-8.1569, 29.9431)
  line L208 (-8.1569, 29.9431) -> (-8.4904, 30.4141)
  line L209 (-8.4904, 30.4141) -> (-9.128, 30.2289)
  line L210 (-9.128, 30.2289) -> (-9.1573, 29.6525)
  line L211 (-9.1573, 29.6525) -> (-9.3228, 29.4234)
  line L212 (-9.3228, 29.4234) -> (-9.523, 29.3087)
  line L213 (-9.523, 29.3087) -> (-9.7523, 29.2839)
  line L214 (-9.7523, 29.2839) -> (-10.0209, 29.3719)
  line L215 (-10.0209, 29.3719) -> (-10.3833, 29.821)
  line L216 (-10.3833, 29.821) -> (-11.0081, 29.5961)
  line L217 (-11.0081, 29.5961) -> (-11.0011, 29.019)
  line L218 (-11.0011, 29.019) -> (-11.1519, 28.78)
  line L219 (-11.1519, 28.78) -> (-11.3445, 28.6529)
  line L220 (-11.3445, 28.6529) -> (-11.5718, 28.6137)
  line L221 (-11.5718, 28.6137) -> (-11.8454, 28.6847)
  line L222 (-11.8454, 28.6847) -> (-12.2353, 29.1102)
  line L223 (-12.2353, 29.1102) -> (-12.8447, 28.8465)
  line L224 (-12.8447, 28.8465) -> (-12.8015, 28.2709)
  line L225 (-12.8015, 28.2709) -> (-12.9371, 28.0229)
  line L226 (-12.9371, 28.0229) -> (-13.1212, 27.884)
  line L227 (-13.1212, 27.884) -> (-13.3457, 27.8307)
  line L228 (-13.3457, 27.8307) -> (-13.6232, 27.8843)
  line L229 (-13.6232, 27.8843) -> (-14.039, 28.2845)
  line L230 (-14.039, 28.2845) -> (-14.6307, 27.983)
  line L231 (-14.6307, 27.983) -> (-14.5514, 27.4113)
  line L232 (-14.5514, 27.4113) -> (-14.6711, 27.1553)
  line L233 (-14.6711, 27.1553) -> (-14.8462, 27.0051)
  line L234 (-14.8462, 27.0051) -> (-15.0668, 26.9378)
  line L235 (-15.0668, 26.9378) -> (-15.3471, 26.9739)
  line L236 (-15.3471, 26.9739) -> (-15.7873, 27.3471)
  line L237 (-15.7873, 27.3471) -> (-16.3589, 27.0091)
  line L238 (-16.3589, 27.0091) -> (-16.2438, 26.4436)
  line L239 (-16.2438, 26.4436) -> (-16.3472, 26.1805)
  line L240 (-16.3472, 26.1805) -> (-16.5126, 26.0196)
  line L241 (-16.5126, 26.0196) -> (-16.7285, 25.9385)
  line L242 (-16.7285, 25.9385) -> (-17.0106, 25.957)
  line L243 (-17.0106, 25.957) -> (-17.4733, 26.3019)
  line L244 (-17.4733, 26.3019) -> (-18.0225, 25.9287)
  line L245 (-18.0225, 25.9287) -> (-17.8722, 25.3714)
  line L246 (-17.8722, 25.3714) -> (-17.9589, 25.1024)
  line L247 (-17.9589, 25.1024) -> (-18.1138, 24.9315)
  line L248 (-18.1138, 24.9315) -> (-18.3242, 24.837)
  line L249 (-18.3242, 24.837) -> (-18.6068, 24.8377)
  line L250 (-18.6068, 24.8377) -> (-19.0903, 25.1528)
  line L251 (-19.0903, 25.1528) -> (-19.615, 24.7458)
  line L252 (-19.615, 24.7458) -> (-19.43, 24.1992)
  line L253 (-19.43, 24.1992) -> (-19.4996, 23.9252)
  line L254 (-19.4996, 23.9252) -> (-19.6435, 23.7449)
  line L255 (-19.6435, 23.7449) -> (-19.8476, 23.6374)
  line L256 (-19.8476, 23.6374) -> (-20.1297, 23.6203)
  line L257 (-20.1297, 23.6203) -> (-20.632, 23.9045)
  line L258 (-20.632, 23.9045) -> (-21.1301, 23.4654)
  line L259 (-21.1301, 23.4654) -> (-20.9111, 22.9314)
  line L260 (-20.9111, 22.9314) -> (-20.9634, 22.6536)
  line L261 (-20.9634, 22.6536) -> (-21.0957, 22.4646)
  line L262 (-21.0957, 22.4646) -> (-21.2926, 22.3445)
  line L263 (-21.2926, 22.3445) -> (-21.5731, 22.3098)
  line L264 (-21.5731, 22.3098) -> (-22.0923, 22.5618)
  line L265 (-22.0923, 22.5618) -> (-22.5618, 22.0923)
  line L266 (-22.5618, 22.0923) -> (-22.3098, 21.5731)
  line L267 (-22.3098, 21.5731) -> (-22.3445, 21.2926)
  line L268 (-22.3445, 21.2926) -> (-22.4646, 21.0957)
  line L269 (-22.4646, 21.0957) -> (-22.6536, 20.9634)
  line L270 (-22.6536, 20.9634) -> (-22.9314, 20.9111)
  line L271 (-22.9314, 20.9111) -> (-23.4654, 21.1301)
  line L272 (-23.4654, 21.1301) -> (-23.9045, 20.632)
  line L273 (-23.9045, 20.632) -> (-23.6203, 20.1297)
  line L274 (-23.6203, 20.1297) -> (-23.6374, 19.8476)
  line L275 (-23.6374, 19.8476) -> (-23.7449, 19.6435)
  line L276 (-23.7449, 19.6435) -> (-23.9252, 19.4996)
  line L277 (-23.9252, 19.4996) -> (-24.1992, 19.43)
  line L278 (-24.1992, 19.43) -> (-24.7458, 19.615)
  line L279 (-24.7458, 19.615) -> (-25.1528, 19.0903)
  line L280 (-25.1528, 19.0903) -> (-24.8377, 18.6068)
  line L281 (-24.8377, 18.6068) -> (-24.837, 18.3242)
  line L282 (-24.837, 18.3242) -> (-24.9315, 18.1138)
  line L283 (-24.9315, 18.1138) -> (-25.1024, 17.9589)
  line L284 (-25.1024, 17.9589) -> (-25.3714, 17.8722)
  line L285 (-25.3714, 17.8722) -> (-25.9287, 18.0225)
  line L286 (-25.9287, 18.0225) -> (-26.3019, 17.4733)
  line L287 (-26.3019, 17.4733) -> (-25.957, 17.0106)
  line L288 (-25.957, 17.0106) -> (-25.9385, 16.7285)
  line L289 (-25.9385, 16.7285) -> (-26.0196, 16.5126)
  line L290 (-26.0196, 16.5126) -> (-26.1805, 16.3472)
  line L291 (-26.1805, 16.3472) -> (-26.4436, 16.2438)
  line L292 (-26.4436, 16.2438) -> (-27.0091, 16.3589)
  line L293 (-27.0091, 16.3589) -> (-27.3471, 15.7873)
  line L294 (-27.3471, 15.7873) -> (-26.9739, 15.3471)
  line L295 (-26.9739, 15.3471) -> (-26.9378, 15.0668)
  line L296 (-26.9378, 15.0668) -> (-27.0051, 14.8462)
  line L297 (-27.0051, 14.8462) -> (-27.1553, 14.6711)
  line L298 (-27.1553, 14.6711) -> (-27.4113, 14.5514)
  line L299 (-27.4113, 14.5514) -> (-27.983, 14.6307)
  line L300 (-27.983, 14.6307) -> (-28.2845, 14.039)
  line L301 (-28.2845, 14.039) -> (-27.8843, 13.6232)
  line L302 (-27.8843, 13.6232) -> (-27.8307, 13.3457)
  line L303 (-27.8307, 13.3457) -> (-27.884, 13.1212)
  line L304 (-27.884, 13.1212) -> (-28.0229, 12.9371)
  line L305 (-28.0229, 12.9371) -> (-28.2709, 12.8015)
  line L306 (-28.2709, 12.8015) -> (-28.8465, 12.8447)
  line L307 (-28.8465, 12.8447) -> (-29.1102, 12.2353)
  line L308 (-29.1102, 12.2353) -> (-28.6847, 11.8454)
  line L309 (-28.6847, 11.8454) -> (-28.6137, 11.5718)
  line L310 (-28.6137, 11.5718) -> (-28.6529, 11.3445)
  line L311 (-28.6529, 11.3445) -> (-28.78, 11.1519)
  line L312 (-28.78, 11.1519) -> (-29.019, 11.0011)
  line L313 (-29.019, 11.0011) -> (-29.5961, 11.0081)
  line L314 (-29.5961, 11.0081) -> (-29.821, 10.3833)
  line L315 (-29.821, 10.3833) -> (-29.3719, 10.0209)
  line L316 (-29.3719, 10.0209) -> (-29.2839, 9.7523)
  line L317 (-29.2839, 9.7523) -> (-29.3087, 9.523)
  line L318 (-29.3087, 9.523) -> (-29.4234, 9.3228)
  line L319 (-29.4234, 9.3228) -> (-29.6525, 9.1573)
  line L320 (-29.6525, 9.1573) -> (-30.2289, 9.128)
  line L321 (-30.2289, 9.128) -> (-30.4141, 8.4904)
  line L322 (-30.4141, 8.4904) -> (-29.9431, 8.1569)
  line L323 (-29.9431, 8.1569) -> (-29.8384, 7.8943)
  line L324 (-29.8384, 7.8943) -> (-29.8488, 7.6639)
  line L325 (-29.8488, 7.6639) -> (-29.9507, 7.4569)
  line L326 (-29.9507, 7.4569) -> (-30.1689, 7.2773)
  line L327 (-30.1689, 7.2773) -> (-30.7424, 7.2119)
  line L328 (-30.7424, 7.2119) -> (-30.8872, 6.5639)
  line L329 (-30.8872, 6.5639) -> (-30.3962, 6.2606)
  line L330 (-30.3962, 6.2606) -> (-30.2752, 6.0052)
  line L331 (-30.2752, 6.0052) -> (-30.2711, 5.7745)
  line L332 (-30.2711, 5.7745) -> (-30.3599, 5.5616)
  line L333 (-30.3599, 5.5616) -> (-30.5664, 5.3686)
  line L334 (-30.5664, 5.3686) -> (-31.1346, 5.2674)
  line L335 (-31.1346, 5.2674) -> (-31.2384, 4.6115)
  line L336 (-31.2384, 4.6115) -> (-30.7293, 4.3397)
  line L337 (-30.7293, 4.3397) -> (-30.5926, 4.0923)
  line L338 (-30.5926, 4.0923) -> (-30.574, 3.8624)
  line L339 (-30.574, 3.8624) -> (-30.6492, 3.6443)
  line L340 (-30.6492, 3.6443) -> (-30.8431, 3.4387)
  line L341 (-30.8431, 3.4387) -> (-31.4039, 3.302)
  line L342 (-31.4039, 3.302) -> (-31.4664, 2.641)
  line L343 (-31.4664, 2.641) -> (-30.9412, 2.4016)
  line L344 (-30.9412, 2.4016) -> (-30.7892, 2.1633)
  line L345 (-30.7892, 2.1633) -> (-30.7562, 1.935)
  line L346 (-30.7562, 1.935) -> (-30.8175, 1.7126)
  line L347 (-30.8175, 1.7126) -> (-30.9982, 1.4953)
  line L348 (-30.9982, 1.4953) -> (-31.5492, 1.3237)
  line L349 (-31.5492, 1.3237) -> (-31.5701, 0.66)
  line L350 (-31.5701, 0.66) -> (-31.0309, 0.454)
  line L351 (-31.0309, 0.454) -> (-30.8642, 0.2258)
  line L352 (-30.8642, 0.2258) -> (-30.817, 0)
  line L353 (-30.817, 0) -> (-30.8642, -0.2258)
  line L354 (-30.8642, -0.2258) -> (-31.0309, -0.454)
  line L355 (-31.0309, -0.454) -> (-31.5701, -0.66)
  line L356 (-31.5701, -0.66) -> (-31.5492, -1.3237)
  line L357 (-31.5492, -1.3237) -> (-30.9982, -1.4953)
  line L358 (-30.9982, -1.4953) -> (-30.8175, -1.7126)
  line L359 (-30.8175, -1.7126) -> (-30.7562, -1.935)
  line L360 (-30.7562, -1.935) -> (-30.7892, -2.1633)
  line L361 (-30.7892, -2.1633) -> (-30.9412, -2.4016)
  line L362 (-30.9412, -2.4016) -> (-31.4664, -2.641)
  line L363 (-31.4664, -2.641) -> (-31.4039, -3.302)
  line L364 (-31.4039, -3.302) -> (-30.8431, -3.4387)
  line L365 (-30.8431, -3.4387) -> (-30.6492, -3.6443)
  line L366 (-30.6492, -3.6443) -> (-30.574, -3.8624)
  line L367 (-30.574, -3.8624) -> (-30.5926, -4.0923)
  line L368 (-30.5926, -4.0923) -> (-30.7293, -4.3397)
  line L369 (-30.7293, -4.3397) -> (-31.2384, -4.6115)
  line L370 (-31.2384, -4.6115) -> (-31.1346, -5.2674)
  line L371 (-31.1346, -5.2674) -> (-30.5664, -5.3686)
  line L372 (-30.5664, -5.3686) -> (-30.3599, -5.5616)
  line L373 (-30.3599, -5.5616) -> (-30.2711, -5.7745)
  line L374 (-30.2711, -5.7745) -> (-30.2752, -6.0052)
  line L375 (-30.2752, -6.0052) -> (-30.3962, -6.2606)
  line L376 (-30.3962, -6.2606) -> (-30.8872, -6.5639)
  line L377 (-30.8872, -6.5639) -> (-30.7424, -7.2119)
  line L378 (-30.7424, -7.2119) -> (-30.1689, -7.2773)
  line L379 (-30.1689, -7.2773) -> (-29.9507, -7.4569)
  line L380 (-29.9507, -7.4569) -> (-29.8488, -7.6639)
  line L381 (-29.8488, -7.6639) -> (-29.8384, -7.8943)
  line L382 (-29.8384, -7.8943) -> (-29.9431, -8.1569)
  line L383 (-29.9431, -8.1569) -> (-30.4141, -8.4904)
  line L384 (-30.4141, -8.4904) -> (-30.2289, -9.128)
  line L385 (-30.2289, -9.128) -> (-29.6525, -9.1573)
  line L386 (-29.6525, -9.1573) -> (-29.4234, -9.3228)
  line L387 (-29.4234, -9.3228) -> (-29.3087, -9.523)
  line L388 (-29.3087, -9.523) -> (-29.2839, -9.7523)
  line L389 (-29.2839, -9.7523) -> (-29.3719, -10.0209)
  line L390 (-29.3719, -10.0209) -> (-29.821, -10.3833)
  line L391 (-29.821, -10.3833) -> (-29.5961, -11.0081)
  line L392 (-29.5961, -11.0081) -> (-29.019, -11.0011)
  line L393 (-29.019, -11.0011) -> (-28.78, -11.1519)
  line L394 (-28.78, -11.1519) -> (-28.6529, -11.3445)
  line L395 (-28.6529, -11.3445) -> (-28.6137, -11.5718)
  line L396 (-28.6137, -11.5718) -> (-28.6847, -11.8454)
  line L397 (-28.6847, -11.8454) -> (-29.1102, -12.2353)
  line L398 (-29.1102, -12.2353) -> (-28.8465, -12.8447)
  line L399 (-28.8465, -12.8447) -> (-28.2709, -12.8015)
  line L400 (-28.2709, -12.8015) -> (-28.0229, -12.9371)
  line L401 (-28.0229, -12.9371) -> (-27.884, -13.1212)
  line L402 (-27.884, -13.1212) -> (-27.8307, -13.3457)
  line L403 (-27.8307, -13.3457) -> (-27.8843, -13.6232)
  line L404 (-27.8843, -13.6232) -> (-28.2845, -14.039)
  line L405 (-28.2845, -14.039) -> (-27.983, -14.6307)
  line L406 (-27.983, -14.6307) -> (-27.4113, -14.5514)
  line L407 (-27.4113, -14.5514) -> (-27.1553, -14.6711)
  line L408 (-27.1553, -14.6711) -> (-27.0051, -14.8462)
  line L409 (-27.0051, -14.8462) -> (-26.9378, -15.0668)
  line L410 (-26.9378, -15.0668) -> (-26.9739, -15.3471)
  line L411 (-26.9739, -15.3471) -> (-27.3471, -15.7873)
  line L412 (-27.3471, -15.7873) -> (-27.0091, -16.3589)
  line L413 (-27.0091, -16.3589) -> (-26.4436, -16.2438)
  line L414 (-26.4436, -16.2438) -> (-26.1805, -16.3472)
  line L415 (-26.1805, -16.3472) -> (-26.0196, -16.5126)
  line L416 (-26.0196, -16.5126) -> (-25.9385, -16.7285)
  line L417 (-25.9385, -16.7285) -> (-25.957, -17.0106)
  line L418 (-25.957, -17.0106) -> (-26.3019, -17.4733)
  line L419 (-26.3019, -17.4733) -> (-25.9287, -18.0225)
  line L420 (-25.9287, -18.0225) -> (-25.3714, -17.8722)
  line L421 (-25.3714, -17.8722) -> (-25.1024, -17.9589)
  line L422 (-25.1024, -17.9589) -> (-24.9315, -18.1138)
  line L423 (-24.9315, -18.1138) -> (-24.837, -18.3242)
  line L424 (-24.837, -18.3242) -> (-24.8377, -18.6068)
  line L425 (-24.8377, -18.6068) -> (-25.1528, -19.0903)
  line L426 (-25.1528, -19.0903) -> (-24.7458, -19.615)
  line L427 (-24.7458, -19.615) -> (-24.1992, -19.43)
  line L428 (-24.1992, -19.43) -> (-23.9252, -19.4996)
  line L429 (-23.9252, -19.4996) -> (-23.7449, -19.6435)
  line L430 (-23.7449, -19.6435) -> (-23.6374, -19.8476)
  line L431 (-23.6374, -19.8476) -> (-23.6203, -20.1297)
  line L432 (-23.6203, -20.1297) -> (-23.9045, -20.632)
  line L433 (-23.9045, -20.632) -> (-23.4654, -21.1301)
  line L434 (-23.4654, -21.1301) -> (-22.9314, -20.9111)
  line L435 (-22.9314, -20.9111) -> (-22.6536, -20.9634)
  line L436 (-22.6536, -20.9634) -> (-22.4646, -21.0957)
  line L437 (-22.4646, -21.0957) -> (-22.3445, -21.2926)
  line L438 (-22.3445, -21.2926) -> (-22.3098, -21.5731)
  line L439 (-22.3098, -21.5731) -> (-22.5618, -22.0923)
  line L440 (-22.5618, -22.0923) -> (-22.0923, -22.5618)
  line L441 (-22.0923, -22.5618) -> (-21.5731, -22.3098)
  line L442 (-21.5731, -22.3098) -> (-21.2926, -22.3445)
  line L443 (-21.2926, -22.3445) -> (-21.0957, -22.4646)
  line L444 (-21.0957, -22.4646) -> (-20.9634, -22.6536)
  line L445 (-20.9634, -22.6536) -> (-20.9111, -22.9314)
  line L446 (-20.9111, -22.9314) -> (-21.1301, -23.4654)
  line L447 (-21.1301, -23.4654) -> (-20.632, -23.9045)
  line L448 (-20.632, -23.9045) -> (-20.1297, -23.6203)
  line L449 (-20.1297, -23.6203) -> (-19.8476, -23.6374)
  line L450 (-19.8476, -23.6374) -> (-19.6435, -23.7449)
  line L451 (-19.6435, -23.7449) -> (-19.4996, -23.9252)
  line L452 (-19.4996, -23.9252) -> (-19.43, -24.1992)
  line L453 (-19.43, -24.1992) -> (-19.615, -24.7458)
  line L454 (-19.615, -24.7458) -> (-19.0903, -25.1528)
  line L455 (-19.0903, -25.1528) -> (-18.6068, -24.8377)
  line L456 (-18.6068, -24.8377) -> (-18.3242, -24.837)
  line L457 (-18.3242, -24.837) -> (-18.1138, -24.9315)
  line L458 (-18.1138, -24.9315) -> (-17.9589, -25.1024)
  line L459 (-17.9589, -25.1024) -> (-17.8722, -25.3714)
  line L460 (-17.8722, -25.3714) -> (-18.0225, -25.9287)
  line L461 (-18.0225, -25.9287) -> (-17.4733, -26.3019)
  line L462 (-17.4733, -26.3019) -> (-17.0106, -25.957)
  line L463 (-17.0106, -25.957) -> (-16.7285, -25.9385)
  line L464 (-16.7285, -25.9385) -> (-16.5126, -26.0196)
  line L465 (-16.5126, -26.0196) -> (-16.3472, -26.1805)
  line L466 (-16.3472, -26.1805) -> (-16.2438, -26.4436)
  line L467 (-16.2438, -26.4436) -> (-16.3589, -27.0091)
  line L468 (-16.3589, -27.0091) -> (-15.7873, -27.3471)
  line L469 (-15.7873, -27.3471) -> (-15.3471, -26.9739)
  line L470 (-15.3471, -26.9739) -> (-15.0668, -26.9378)
  line L471 (-15.0668, -26.9378) -> (-14.8462, -27.0051)
  line L472 (-14.8462, -27.0051) -> (-14.6711, -27.1553)
  line L473 (-14.6711, -27.1553) -> (-14.5514, -27.4113)
  line L474 (-14.5514, -27.4113) -> (-14.6307, -27.983)
  line L475 (-14.6307, -27.983) -> (-14.039, -28.2845)
  line L476 (-14.039, -28.2845) -> (-13.6232, -27.8843)
  line L477 (-13.6232, -27.8843) -> (-13.3457, -27.8307)
  line L478 (-13.3457, -27.8307) -> (-13.1212, -27.884)
  line L479 (-13.1212, -27.884) -> (-12.9371, -28.0229)
  line L480 (-12.9371, -28.0229) -> (-12.8015, -28.2709)
  line L481 (-12.8015, -28.2709) -> (-12.8447, -28.8465)
  line L482 (-12.8447, -28.8465) -> (-12.2353, -29.1102)
  line L483 (-12.2353, -29.1102) -> (-11.8454, -28.6847)
  line L484 (-11.8454, -28.6847) -> (-11.5718, -28.6137)
  line L485 (-11.5718, -28.6137) -> (-11.3445, -28.6529)
  line L486 (-11.3445, -28.6529) -> (-11.1519, -28.78)
  line L487 (-11.1519, -28.78) -> (-11.0011, -29.019)
  line L488 (-11.0011, -29.019) -> (-11.0081, -29.5961)
  line L489 (-11.0081, -29.5961) -> (-10.3833, -29.821)
  line L490 (-10.3833, -29.821) -> (-10.0209, -29.3719)
  line L491 (-10.0209, -29.3719) -> (-9.7523, -29.2839)
  line L492 (-9.7523, -29.2839) -> (-9.523, -29.3087)
  line L493 (-9.523, -29.3087) -> (-9.3228, -29.4234)
  line L494 (-9.3228, -29.4234) -> (-9.1573, -29.6525)
  line L495 (-9.1573, -29.6525) -> (-9.128, -30.2289)
  line L496 (-9.128, -30.2289) -> (-8.4904, -30.4141)
  line L497 (-8.4904, -30.4141) -> (-8.1569, -29.9431)
  line L498 (-8.1569, -29.9431) -> (-7.8943, -29.8384)
  line L499 (-7.8943, -29.8384) -> (-7.6639, -29.8488)
  line L500 (-7.6639, -29.8488) -> (-7.4569, -29.9507)
  line L501 (-7.4569, -29.9507) -> (-7.2773, -30.1689)
  line L502 (-7.2773, -30.1689) -> (-7.2119, -30.7424)
  line L503 (-7.2119, -30.7424) -> (-6.5639, -30.8872)
  line L504 (-6.5639, -30.8872) -> (-6.2606, -30.3962)
  line L505 (-6.2606, -30.3962) -> (-6.0052, -30.2752)
  line L506 (-6.0052, -30.2752) -> (-5.7745, -30.2711)
  line L507 (-5.7745, -30.2711) -> (-5.5616, -30.3599)
  line L508 (-5.5616, -30.3599) -> (-5.3686, -30.5664)
  line L509 (-5.3686, -30.5664) -> (-5.2674, -31.1346)
  line L510 (-5.2674, -31.1346) -> (-4.6115, -31.2384)
  line L511 (-4.6115, -31.2384) -> (-4.3397, -30.7293)
  line L512 (-4.3397, -30.7293) -> (-4.0923, -30.5926)
  line L513 (-4.0923, -30.5926) -> (-3.8624, -30.574)
  line L514 (-3.8624, -30.574) -> (-3.6443, -30.6492)
  line L515 (-3.6443, -30.6492) -> (-3.4387, -30.8431)
  line L516 (-3.4387, -30.8431) -> (-3.302, -31.4039)
  line L517 (-3.302, -31.4039) -> (-2.641, -31.4664)
  line L518 (-2.641, -31.4664) -> (-2.4016, -30.9412)
  line L519 (-2.4016, -30.9412) -> (-2.1633, -30.7892)
  line L520 (-2.1633, -30.7892) -> (-1.935, -30.7562)
  line L521 (-1.935, -30.7562) -> (-1.7126, -30.8175)
  line L522 (-1.7126, -30.8175) -> (-1.4953, -30.9982)
  line L523 (-1.4953, -30.9982) -> (-1.3237, -31.5492)
  line L524 (-1.3237, -31.5492) -> (-0.66, -31.5701)
  line L525 (-0.66, -31.5701) -> (-0.454, -31.0309)
  line L526 (-0.454, -31.0309) -> (-0.2258, -30.8642)
  line L527 (-0.2258, -30.8642) -> (0, -30.817)
  line L528 (0, -30.817) -> (0.2258, -30.8642)
  line L529 (0.2258, -30.8642) -> (0.454, -31.0309)
  line L530 (0.454, -31.0309) -> (0.66, -31.5701)
  line L531 (0.66, -31.5701) -> (1.3237, -31.5492)
  line L532 (1.3237, -31.5492) -> (1.4953, -30.9982)
  line L533 (1.4953, -30.9982) -> (1.7126, -30.8175)
  line L534 (1.7126, -30.8175) -> (1.935, -30.7562)
  line L535 (1.935, -30.7562) -> (2.1633, -30.7892)
  line L536 (2.1633, -30.7892) -> (2.4016, -30.9412)
  line L537 (2.4016, -30.9412) -> (2.641, -31.4664)
  line L538 (2.641, -31.4664) -> (3.302, -31.4039)
  line L539 (3.302, -31.4039) -> (3.4387, -30.8431)
  line L540 (3.4387, -30.8431) -> (3.6443, -30.6492)
  line L541 (3.6443, -30.6492) -> (3.8624, -30.574)
  line L542 (3.8624, -30.574) -> (4.0923, -30.5926)
  line L543 (4.0923, -30.5926) -> (4.3397, -30.7293)
  line L544 (4.3397, -30.7293) -> (4.6115, -31.2384)
  line L545 (4.6115, -31.2384) -> (5.2674, -31.1346)
  line L546 (5.2674, -31.1346) -> (5.3686, -30.5664)
  line L547 (5.3686, -30.5664) -> (5.5616, -30.3599)
  line L548 (5.5616, -30.3599) -> (5.7745, -30.2711)
  line L549 (5.7745, -30.2711) -> (6.0052, -30.2752)